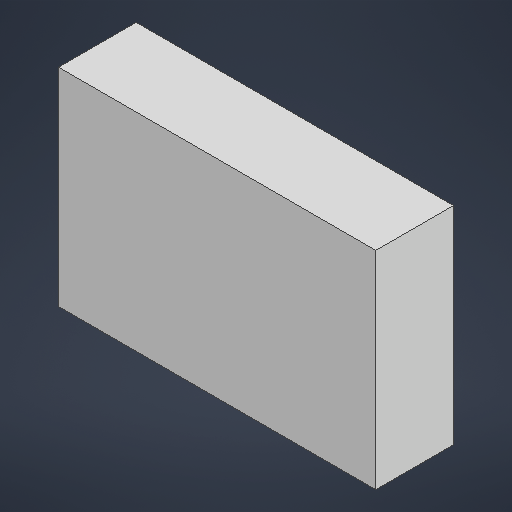
# Autodesk Inventor part: DUMMY-DF2301Q
Saved by Autodesk Inventor 2027.1 (Build 311270010, 270A)
## iProperties
Created: 2026-10-28
Part Number: DUMMY-DF2301Q
Material: Generic
Description: DF2301Q voice module
Document SubType Name: Modeling
Designer: shyan
Density: 1 g/cm^3
Appearance: Default
Mass: 12 g
Author: shyan
Autodesk Inventor part; units mm, degrees
ref_plane "YZ Plane" through (0, 0, 0) normal (1, 0, 0) x (0, 1, 0)
ref_plane "XZ Plane" through (0, 0, 0) normal (0, 1, 0) x (-1, 0, 0)
ref_plane "XY Plane" through (0, 0, 0) normal (0, 0, 1) x (1, 0, 0)
sketch "sk_body" plane through (0, 0, 0) normal (0, 0, 1) x (1, 0, 0)
  line L0 (-24.5, -16) -> (24.5, -16)
  line L1 (24.5, -16) -> (24.5, 16)
  line L2 (24.5, 16) -> (-24.5, 16)
  line L3 (-24.5, 16) -> (-24.5, -16)
  line L4 (-34.3, 0) -> (34.3, 0) construction
  line L5 (0, -22.4) -> (0, 22.4) construction
  point P0 (0, 0)
  dimension "d0" = 49
  dimension "d1" = 32
  constraints: 8 end point, 2 parallel, 1 horizontal, 1 perpendicular, 2 other
  measures "d0" distance of L0.start L0.end
  measures "d1" distance of L0.end L1.end
extrude "Body" add sketch "sk_body" along normal blind 12
equation "\"d0\" = df_W"
equation "\"d1\" = df_D"
equation "\"d2\" = df_H"
equation "\"df_W\" = 49"
equation "\"df_D\" = 32"
equation "\"df_H\" = 12"
body "Solid1"
